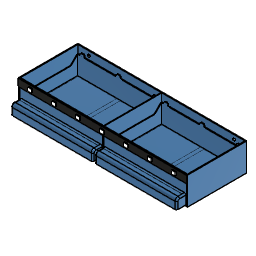
Medium_Drawer_Assembly (Autodesk Fusion 360 design; units mm, degrees)
Autodesk Fusion 360 part; units mm, degrees
note: some values were not read from the file. Set by a fixed rule: which face or edge a step refers to.
sketch "Bottom" plane through (0, 0, 0) normal (0, 0, 1) x (1, 0, 0) in component "Medium_Holder_PRINT v1"
  line L0 (0, 0) -> (232.6, 0)
  line L1 (232.6, 0) -> (232.6, 81.6)
  line L2 (232.6, 81.6) -> (0, 81.6)
  line L3 (0, 81.6) -> (0, 0)
  line L4 (1.2, 80.4) -> (231.4, 80.4)
  line L5 (231.4, 80.4) -> (231.4, 1.2)
  line L6 (231.4, 1.2) -> (1.2, 1.2)
  line L7 (1.2, 1.2) -> (1.2, 80.4)
  line L8 (3.2, 3.2) -> (3.2, 78.4)
  line L9 (33.4, 80.4) -> (34.2, 80.4)
  line L10 (34.2, 1.2) -> (33.4, 1.2)
  line L11 (66.4, 80.4) -> (67.2, 80.4)
  line L12 (67.2, 1.2) -> (66.4, 1.2)
  line L13 (99.4, 80.4) -> (100.2, 80.4)
  line L14 (100.2, 1.2032) -> (99.4, 1.2032)
  line L15 (132.4, 80.4) -> (133.2, 80.4)
  line L16 (133.2, 1.2) -> (132.4, 1.2)
  line L17 (165.4, 80.4) -> (166.2, 80.4)
  line L18 (166.2, 1.2) -> (165.4, 1.2)
  line L19 (198.4, 80.4) -> (199.2, 80.4)
  line L20 (199.2, 1.2) -> (198.4, 1.2)
  line L21 (229.4, 78.4) -> (229.4, 3.2)
  line L22 (231.4, 80.4) -> (232.2, 80.4)
  line L23 (232.2, 1.2) -> (231.4, 1.2)
  line L24 (115.9, 78.4) -> (115.9, 3.2)
  line L25 (116.7, 78.4) -> (116.7, 3.2)
  line L26 (116.7, 78.4) -> (116.7, 80.4)
  line L27 (115.9, 78.4) -> (115.9, 80.4)
  line L28 (116.7, 3.2) -> (116.7, 1.2)
  line L29 (115.9, 3.2) -> (115.9, 1.2)
  line L30 (113.9, 78.4) -> (113.9, 3.2)
  line L31 (3.2, 78.4) -> (113.9, 78.4)
  line L32 (113.9, 3.2) -> (3.2, 3.2)
  line L33 (229.4, 78.4) -> (118.7, 78.4)
  line L34 (118.7, 78.4) -> (118.7, 3.2)
  line L35 (229.4, 3.2) -> (118.7, 3.2)
  line L36 (56.2, 78.4) -> (56.2, 3.2)
  line L37 (61.2, 78.4) -> (61.2, 3.2)
  line L38 (171.7, 78.4) -> (171.7, 3.2)
  line L39 (176.7, 3.2) -> (176.7, 78.4)
  dimension "d1_3" = 1.2
  dimension "d2_3" = 1.2
  dimension "d3_3" = 1.2
  dimension "d4_3" = 1.2
  dimension "d5_3" = 2
  dimension "d8_1" = 81.6
  dimension "d52_2" = 2
  dimension "d173" = 112.7
  dimension "d174" = 112.7
  dimension "d175" = 0.8
  dimension "d190" = 2
  dimension "d191" = 2
  dimension "d192" = 2
  dimension "d193" = 2
  dimension "d194" = 2
  dimension "d195" = 2
  dimension "d203" = 5
  dimension "d204" = 53
  dimension "d206" = 5
  dimension "d207" = 53
  constraint horizontal L0
  constraint vertical L1
  constraint horizontal L2
  constraint vertical L3
  constraint coincident L0.start L3.end
  constraint horizontal L4
  constraint vertical L5
  constraint horizontal L6
  constraint vertical L7
  constraint vertical L8
  constraint horizontal L9
  constraint coincident L6 L10.start
  constraint coincident L4 L9.start
  constraint horizontal L11
  constraint horizontal L12
  constraint coincident L4 L11.start
  constraint horizontal L13
  constraint horizontal L14
  constraint coincident L4 L13.start
  constraint horizontal L15
  constraint horizontal L16
  constraint coincident L4 L15.start
  constraint horizontal L17
  constraint horizontal L18
  constraint coincident L4 L17.start
  constraint horizontal L19
  constraint horizontal L20
  constraint coincident L4 L19.start
  constraint vertical L21
  constraint horizontal L22
  constraint horizontal L23
  constraint coincident L4 L5.start
  constraint coincident L4 L26.end
  constraint perpendicular L4 L26
  constraint coincident L4 L27.end
  constraint perpendicular L4 L27
  constraint coincident L6 L28.end
  constraint perpendicular L6 L28
  constraint coincident L6 L29.end
  constraint perpendicular L6 L29
  constraint perpendicular L30 L31
  constraint perpendicular L8 L32
  constraint perpendicular L24 L33
  constraint perpendicular L34 L35
  constraint coincident L31 L36.start
  constraint coincident L32 L36.end
  constraint perpendicular L32 L36
  constraint coincident L31 L37.start
  constraint coincident L32 L37.end
  constraint perpendicular L32 L37
  constraint coincident L33 L38.start
  constraint coincident L35 L38.end
  constraint perpendicular L35 L38
  constraint coincident L35 L39.start
  constraint coincident L33 L39.end
  constraint perpendicular L33 L39
  measures "d1_3" distance of L3 L7
  measures "d2_3" distance of L2 L4
  measures "d3_3" distance of L0 L6
  measures "d4_3" distance of L1 L5
  measures "d5_3" distance of L7 L8
  measures "d8_1" distance of L0.start L2.end
  measures "d52_2" distance of L5 L21
  measures "d173" distance of L8 L24
  measures "d174" distance of L21 L25
  measures "d175" distance of L24 L25
  measures "d190" distance of L24 L30
  measures "d191" distance of L4 L31
  measures "d192" distance of L6 L32
  measures "d193" distance of L25 L34
  measures "d194" distance of L6 L35
  measures "d195" distance of L4 L33
  measures "d203" distance of L36 L37
  measures "d204" distance of L8 L36
  measures "d206" distance of L38 L39
  measures "d207" distance of L34 L38
extrude "Extrude2" add sketch "Bottom" along normal blind 38.2 contours L0 L1 L2 L3 | L4 L6 L24 L25 L26 L27 L28 L29 makes body 1 in component "Medium_Holder_PRINT v1"
sketch "Front" plane through (0, 0, 0) normal (0, -1, 0) x (1, 0, 0) in component "Medium_Holder_PRINT v1"
  line L0 (0, 0) -> (232.6, 0)
  line L1 (232.6, 0) -> (232.6, 38.2)
  line L2 (232.6, 38.2) -> (0, 38.2)
  line L3 (0, 38.2) -> (0, 0)
  line L4 (1.2, 28.2) -> (33.4, 28.2)
  line L5 (33.4, 1.2) -> (1.2, 1.2)
  line L6 (1.2, 1.2) -> (1.2, 28.2)
  line L7 (1.2, 0) -> (1.2, 38.2)
  line L8 (231.4, 28.2) -> (231.4, 1.2)
  line L9 (33.4, 28.2) -> (231.4, 28.2)
  line L10 (231.4, 1.2) -> (33.4, 1.2)
  dimension "d80" = 27
  dimension "d83" = 10
  dimension "d91" = 27
  dimension "d294" = 1.2
  constraint horizontal L4
  constraint horizontal L5
  constraint vertical L6
  constraint collinear L6 L7
  constraint vertical L8
  constraint perpendicular L8 L9
  measures "d80" distance of L4.start L5.end
  measures "d83" distance of L2 L4
  measures "d91" distance of L8.start L8.end
  measures "d294" distance of L1 L8
sketch "Back" plane through (0, 80.4, 0) normal (0, -1, 0) x (1, 0, 0) in component "Medium_Holder_PRINT v1"
  line L0 (231.4, 0) -> (231.4, 38.2)
  line L1 (115.9, 38.2) -> (1.2, 38.2)
  line L2 (1.2, 38.2) -> (1.2, 0)
  line L3 (3.2, 23) -> (3.2, 7)
  line L4 (115.9, 0) -> (115.9, 38.2)
  line L5 (116.7, 38.2) -> (116.7, 0)
  line L6 (231.4, 38.2) -> (116.7, 38.2)
  line L7 (116.7, 0) -> (231.4, 0)
  line L8 (1.2, 0) -> (115.9, 0)
  line L9 (3.2, 23) -> (6.7355, 26.5355)
  line L10 (3.2, 23) -> (8.2, 23) construction
  line L11 (6.7355, 26.5355) -> (31.7355, 26.5355)
  line L12 (31.7355, 26.5355) -> (35.2711, 23)
  line L13 (31.7355, 26.5355) -> (36.7355, 26.5355) construction
  line L14 (35.2711, 23) -> (35.2711, 7)
  line L15 (35.2711, 7) -> (31.7355, 3.4645)
  line L16 (3.2, 7) -> (6.7355, 3.4645)
  line L17 (3.2, 7) -> (8.2, 7) construction
  line L18 (6.7355, 3.4645) -> (31.7355, 3.4645)
  line L19 (43.6066, 26.5355) -> (68.6066, 26.5355)
  line L20 (40.0711, 23) -> (43.6066, 26.5355)
  line L21 (40.0711, 23) -> (40.0711, 7)
  line L22 (40.0711, 7) -> (43.6066, 3.4645)
  line L23 (43.6066, 3.4645) -> (68.6066, 3.4645)
  line L24 (72.1421, 7) -> (68.6066, 3.4645)
  line L25 (72.1421, 23) -> (72.1421, 7)
  line L26 (68.6066, 26.5355) -> (72.1421, 23)
  line L27 (80.4777, 26.5355) -> (105.4777, 26.5355)
  line L28 (76.9421, 23) -> (80.4777, 26.5355)
  line L29 (76.9421, 23) -> (76.9421, 7)
  line L30 (76.9421, 7) -> (80.4777, 3.4645)
  line L31 (80.4777, 3.4645) -> (105.4777, 3.4645)
  line L32 (109.0132, 7) -> (105.4777, 3.4645)
  line L33 (109.0132, 23) -> (109.0132, 7)
  line L34 (105.4777, 26.5355) -> (109.0132, 23)
  line L35 (127.1223, 26.5355) -> (152.1223, 26.5355)
  line L36 (123.5868, 23) -> (127.1223, 26.5355)
  line L37 (123.5868, 23) -> (123.5868, 7)
  line L38 (123.5868, 7) -> (127.1223, 3.4645)
  line L39 (127.1223, 3.4645) -> (152.1223, 3.4645)
  line L40 (155.6579, 7) -> (152.1223, 3.4645)
  line L41 (155.6579, 23) -> (155.6579, 7)
  line L42 (152.1223, 26.5355) -> (155.6579, 23)
  line L43 (163.9934, 26.5355) -> (188.9934, 26.5355)
  line L44 (160.4579, 23) -> (163.9934, 26.5355)
  line L45 (160.4579, 23) -> (160.4579, 7)
  line L46 (160.4579, 7) -> (163.9934, 3.4645)
  line L47 (163.9934, 3.4645) -> (188.9934, 3.4645)
  line L48 (192.5289, 7) -> (188.9934, 3.4645)
  line L49 (192.5289, 23) -> (192.5289, 7)
  line L50 (188.9934, 26.5355) -> (192.5289, 23)
  line L51 (200.8645, 26.5355) -> (225.8645, 26.5355)
  line L52 (197.3289, 23) -> (200.8645, 26.5355)
  line L53 (197.3289, 23) -> (197.3289, 7)
  line L54 (197.3289, 7) -> (200.8645, 3.4645)
  line L55 (200.8645, 3.4645) -> (225.8645, 3.4645)
  line L56 (229.4, 7) -> (225.8645, 3.4645)
  line L57 (229.4, 23) -> (229.4, 7)
  line L58 (225.8645, 26.5355) -> (229.4, 23)
  line L59 (232.6, 0) -> (232.6, 38.2)
  dimension "d102" = 2
  dimension "d211" = 16
  dimension "d214" = 7
  dimension "d216" = 5
  dimension "d217" = 45
  dimension "d218" = 25
  dimension "d219" = 45
  dimension "d220" = 5
  dimension "d221" = 135
  dimension "d222" = 5
  dimension "d223" = 45
  dimension "d224" = 5
  dimension "d225" = 16
  dimension "d226" = 5
  dimension "d227" = 25
  dimension "d228" = 5
  dimension "d229" = 135
  dimension "d230" = 5
  dimension "d231" = 5
  dimension "d232" = 16
  dimension "d233" = 5
  dimension "d234" = 25
  dimension "d235" = 5
  dimension "d236" = 135
  dimension "d237" = 5
  dimension "d238" = 5
  dimension "d239" = 16
  dimension "d240" = 5
  dimension "d241" = 25
  dimension "d242" = 5
  dimension "d243" = 135
  dimension "d244" = 5
  dimension "d245" = 5
  dimension "d246" = 16
  dimension "d247" = 5
  dimension "d248" = 25
  dimension "d249" = 5
  dimension "d250" = 135
  dimension "d251" = 5
  dimension "d252" = 5
  dimension "d253" = 16
  dimension "d254" = 5
  dimension "d255" = 25
  dimension "d256" = 5
  dimension "d257" = 135
  dimension "d258" = 5
  dimension "d259" = 5
  dimension "d260" = 4.8
  dimension "d261" = 4.8
  dimension "d262" = 4.8
  dimension "d263" = 4.8
  dimension "d264" = 23.0711
  dimension "d265" = 3.4645
  dimension "d266" = 32.0711
  dimension "d267" = 3.4645
  dimension "d268" = 3.2
  dimension "d269" = 6.8868
  dimension "d270" = 135
  dimension "d272" = 135
  dimension "d273" = 23.0711
  dimension "d274" = 135
  dimension "d275" = 23.0711
  dimension "d279" = 135
  dimension "d280" = 23.0711
  dimension "d281" = 135
  dimension "d283" = 32.0711
  dimension "d284" = 32.0711
  dimension "d285" = 135
  dimension "d286" = 135
  dimension "d287" = 23.0711
  dimension "d288" = 135
  dimension "d290" = 3.4645
  dimension "d292" = 135
  dimension "d297" = 3.4645
  dimension "d298" = 3.4645
  constraint parallel L2 L3
  constraint horizontal L10
  constraint horizontal L11
  constraint horizontal L13
  constraint vertical L14
  constraint horizontal L17
  constraint horizontal L19
  constraint vertical L25
  constraint horizontal L27
  constraint vertical L33
  constraint horizontal L35
  constraint vertical L41
  constraint horizontal L43
  constraint vertical L49
  constraint horizontal L51
  constraint vertical L57
  measures "d102" distance of L2 L3
  measures "d211" distance of L3.end L3.start
  measures "d214" distance of L3.end L8
  measures "d216" distance of L3.start L9.end
  measures "d217" angle of L9 L10
  measures "d218" distance of L9.end L11.end
  measures "d219" angle of L12 L13
  measures "d220" distance of L11.end L12.end
  measures "d221" angle of L14 L15
  measures "d222" distance of L14.end L15.end
  measures "d223" angle of L16 L17
  measures "d224" distance of L3.end L16.end
  measures "d225" distance of L20.start L21.end
  measures "d226" distance of L19.start L20.start
  measures "d227" distance of L19.start L19.end
  measures "d228" distance of L25.start L19.end
  measures "d229" angle of L24 L25
  measures "d230" distance of L23.end L24.start
  measures "d231" distance of L22.end L21.end
  measures "d232" distance of L28.start L29.end
  measures "d233" distance of L27.start L28.start
  measures "d234" distance of L27.start L27.end
  measures "d235" distance of L33.start L27.end
  measures "d236" angle of L32 L33
  measures "d237" distance of L31.end L32.start
  measures "d238" distance of L30.end L29.end
  measures "d239" distance of L36.start L37.end
  measures "d240" distance of L35.start L36.start
  measures "d241" distance of L35.start L35.end
  measures "d242" distance of L41.start L35.end
  measures "d243" angle of L40 L41
  measures "d244" distance of L39.end L40.start
  measures "d245" distance of L38.end L37.end
  measures "d246" distance of L44.start L45.end
  measures "d247" distance of L43.start L44.start
  measures "d248" distance of L43.start L43.end
  measures "d249" distance of L49.start L43.end
  measures "d250" angle of L48 L49
  measures "d251" distance of L47.end L48.start
  measures "d252" distance of L46.end L45.end
  measures "d253" distance of L52.start L53.end
  measures "d254" distance of L51.start L52.start
  measures "d255" distance of L51.start L51.end
  measures "d256" distance of L57.start L51.end
  measures "d257" angle of L56 L57
  measures "d258" distance of L55.end L56.start
  measures "d259" distance of L54.end L53.end
  measures "d260" distance of L14 L21
  measures "d261" distance of L25 L29
  measures "d262" distance of L49 L53
  measures "d263" distance of L41 L45
  measures "d264" distance of L35 L39
  measures "d265" distance of L7 L39
  measures "d266" distance of L37 L41
  measures "d267" distance of L7 L47
  measures "d268" distance of L57 L59
  measures "d269" distance of L5 L37
  measures "d270" angle of L43 L44
  measures "d272" angle of L43 L50
  measures "d273" distance of L43 L47
  measures "d274" angle of L51 L52
  measures "d275" distance of L51 L55
  measures "d279" angle of L35 L36
  measures "d280" distance of L27 L31
  measures "d281" angle of L27 L34
  measures "d283" distance of L29 L33
  measures "d284" distance of L21 L25
  measures "d285" angle of L19 L20
  measures "d286" angle of L19 L26
  measures "d287" distance of L19 L23
  measures "d288" angle of L20 L21
  measures "d290" distance of L8 L23
  measures "d292" angle of L15 L18
  measures "d297" distance of L8 L31
  measures "d298" distance of L7 L55
sketch "Mounting" plane through (0, 80.4, 0) normal (0, -1, 0) x (1, 0, 0) in component "Medium_Holder_PRINT v1"
  line L0 (231.4, 0) -> (231.4, 38.2)
  line L1 (115.9, 38.2) -> (1.2, 38.2)
  line L2 (1.2, 38.2) -> (1.2, 0)
  circle A0 centre (216.3, 32.2) radius 2
  circle A1 centre (16.3, 32.2) radius 2
  line L3 (115.9, 0) -> (115.9, 38.2)
  line L4 (116.7, 38.2) -> (116.7, 0)
  line L5 (231.4, 38.2) -> (116.7, 38.2)
  line L6 (116.7, 0) -> (231.4, 0)
  line L7 (1.2, 0) -> (115.9, 0)
  dimension "d165" = 4
  dimension "d166" = 4
  dimension "d167" = 15.1
  dimension "d168" = 6
  dimension "d169" = 15.1
  dimension "d170" = 6
  measures "d165" diameter of A0
  measures "d166" diameter of A1
  measures "d167" distance of L2 A1.centre
  measures "d168" distance of L1 A1.centre
  measures "d169" distance of L0 A0.centre
  measures "d170" distance of L1 A0.centre
extrude "Extrude9" cut sketch "Front" against normal up to surface (1.2 mm away) contours L4 L5 L6 L7 L8 L9 L10 bodies 1 in component "Medium_Holder_PRINT v1"
extrude "Extrude10" cut sketch "Back" against normal blind 1.2 contours L3 L9 L11 L12 L14 L15 L16 L18 | L19 L20 L21 L22 L23 L24 L25 L26 | L27 L28 L29 L30 L31 L32 L33 L34 | L35 L36 L37 L38 L39 L40 L41 L42 | L43 L44 L45 L46 L47 L48 L49 L50 | L51 L52 L53 L54 L55 L56 L57 L58 bodies 1 in component "Medium_Holder_PRINT v1"
extrude "Extrude11" cut sketch "Mounting" against normal blind 1.2 contours A0 | A1 bodies 1 in component "Medium_Holder_PRINT v1"
extrude "Extrude12" add sketch "Bottom" along normal up to surface (1.2 mm away) contours L4 L6 L7 L9 L10 L11 L12 L13 L24 L27 L29 bodies 1 in component "Medium_Holder_PRINT v1"
extrude "Extrude13" add sketch "Bottom" along normal up to surface (1.2 mm away) contours L4 L5 L6 L15 L16 L17 L18 L19 L20 L25 L26 L28 | L31 L32 L36 L37 bodies 1 in component "Medium_Holder_PRINT v1"
extrude "Extrude14" add 1 faces at (116.1667, 1.2, 19.2) along direction (0, -1, 0) up to surface (1.2 mm away) on bodies 1 bodies 1 in component "Medium_Holder_PRINT v1"
extrude "Extrude15" add sketch "Bottom" along normal blind 1.2 contours L33 L35 L38 L39 bodies 1 in component "Medium_Holder_PRINT v1"
sketch "Sketch1" plane through (0, 0, 0) normal (0, 0, 1) x (1, 0, 0) in component "Medium_Drawer_PRINT v1"
  line L0 (0, 0) -> (113.9, 0)
  line L1 (113.9, 0) -> (113.9, 80)
  line L2 (113.9, 80) -> (0, 80)
  line L3 (0, 80) -> (0, 0)
  dimension "d1_1" = 113.9
  dimension "d2_1" = 80
  constraint horizontal L0
  constraint vertical L1
  constraint horizontal L2
  constraint vertical L3
  constraint coincident L0.start L3.end
  measures "d1_1" distance of L0.start L0.end
  measures "d2_1" distance of L0.end L1.end
extrude "Extrude1" add sketch "Sketch1" along normal blind 26.2 separate body makes body 2 in component "Medium_Drawer_PRINT v1"
shell "Shell1" thickness 0.8 removed faces 1 at (37.9667, 53.3333, 26.2) on bodies 2 in component "Medium_Drawer_PRINT v1"
ref_plane "WorkPlane1" through (95.5, 40, 13.1) normal (1, 0, 0) x (0, 1, 0) in component "Medium_Drawer_PRINT v1"
sketch "Sketch3" plane through (0, 80, 0) normal (0, 1, 0) x (-1, 0, 0) in component "Medium_Drawer_PRINT v1"
  line L0 (-113.9, 0) -> (0, 0)
  line L1 (0, 0) -> (0, 26.2)
  line L2 (0, 26.2) -> (-113.9, 26.2)
  line L3 (-113.9, 26.2) -> (-113.9, 0)
  line L4 (-56.95, 26.2) -> (-56.95, 0) construction
  line L5 (-109.65, 27.45) -> (-109.65, 28.45)
  line L6 (-108.4, 29.7) -> (-105.4, 29.7)
  line L7 (-104.15, 28.45) -> (-104.15, 27.45)
  line L8 (-110.9, 26.2) -> (-102.9, 26.2)
  arc A0 (-110.9, 26.2) -> (-109.65, 27.45) centre (-110.9, 27.45) ccw
  arc A1 (-108.4, 29.7) -> (-109.65, 28.45) centre (-108.4, 28.45) ccw
  arc A2 (-104.15, 28.45) -> (-105.4, 29.7) centre (-105.4, 28.45) ccw
  arc A3 (-104.15, 27.45) -> (-102.9, 26.2) centre (-102.9, 27.45) ccw
  arc A4 (-4.25, 28.45) -> (-5.5, 29.7) centre (-5.5, 28.45) ccw
  line L9 (-5.5, 29.7) -> (-8.5, 29.7)
  arc A5 (-11, 26.2) -> (-9.75, 27.45) centre (-11, 27.45) ccw
  arc A6 (-4.25, 27.45) -> (-3, 26.2) centre (-3, 27.45) ccw
  line L10 (-4.25, 27.45) -> (-4.25, 28.45)
  line L11 (-3, 26.2) -> (-11, 26.2)
  arc A7 (-8.5, 29.7) -> (-9.75, 28.45) centre (-8.5, 28.45) ccw
  line L12 (-9.75, 28.45) -> (-9.75, 27.45)
  line L13 (-58.25, 29.7) -> (-55.25, 29.7)
  arc A8 (-58.25, 29.7) -> (-59.5, 28.45) centre (-58.25, 28.45) ccw
  line L14 (-59.5, 27.45) -> (-59.5, 28.45)
  arc A9 (-60.75, 26.2) -> (-59.5, 27.45) centre (-60.75, 27.45) ccw
  arc A10 (-54, 27.45) -> (-52.75, 26.2) centre (-52.75, 27.45) ccw
  line L15 (-60.75, 26.2) -> (-52.75, 26.2)
  line L16 (-54, 28.45) -> (-54, 27.45)
  arc A11 (-54, 28.45) -> (-55.25, 29.7) centre (-55.25, 28.45) ccw
  point P0 (-106.9, 29.7)
  point P1 (-7, 29.7)
  dimension "d18_1" = 7
  dimension "d19_1" = 3.5
  dimension "d20_1" = 5.5
  dimension "d21_1" = 1.25
  dimension "d62" = 3.5
  dimension "d63" = 5.5
  dimension "d64" = 1.25
  dimension "d65" = 114.3
  dimension "d66" = 44.65
  dimension "d67" = 44.8
  dimension "d68" = 8
  dimension "d69" = 1.25
  dimension "d70" = 3
  dimension "d71" = 1.25
  dimension "d72" = 1.25
  dimension "d73" = 1.25
  dimension "d74" = 3.5
  constraint midpoint L2 L4.start
  constraint perpendicular L2 L4
  constraint coincident L0 L4.end
  constraint horizontal L6
  constraint tangent L6 A1
  constraint tangent L5 A1
  constraint tangent L5 A0
  constraint tangent L6 A2
  constraint tangent L7 A2
  constraint tangent L7 A3
  constraint tangent L8 A3
  constraint tangent L8 A0
  constraint equal A0 A1
  constraint equal A1 A2
  constraint equal A2 A3
  constraint collinear L2 L8
  constraint vertical L7
  constraint vertical L5
  constraint midpoint L6 P0
  constraint symmetric L4 L5.start A6.start
  constraint symmetric L4 L5.end A4.start
  constraint symmetric L4 L6.start A4.end
  constraint symmetric L4 L6.end L9.end
  constraint symmetric L4 L7.start A7.end
  constraint symmetric L4 L7.end A5.end
  constraint symmetric L4 L8.start A6.end
  constraint symmetric L4 L8.end A5.start
  constraint symmetric L4 P0 P1
  constraint symmetric L4 A0 A6
  constraint symmetric L4 A1 A4
  constraint symmetric L4 A2 A7
  constraint symmetric L4 A3 A5
  constraint horizontal L13
  constraint tangent L13 A8
  constraint tangent A8 L14
  constraint tangent L14 A9
  constraint tangent L13 A11
  constraint tangent L16 A11
  constraint tangent A10 L16
  constraint tangent A10 L15
  constraint tangent A9 L15
  constraint equal A8 A9
  constraint equal A8 A11
  constraint equal A10 A11
  constraint vertical L16
  constraint vertical L14
  measures "d18_1" distance of L3 P0
  measures "d19_1" distance of L6 L8
  measures "d20_1" distance of L5 L7
  measures "d21_1" radius of A0
  measures "d62" distance of L13 L15
  measures "d63" distance of L14 L16
  measures "d64" radius of A9
  measures "d66" distance of L7 L14
  measures "d68" distance of A9.start A10.end
  measures "d69" radius of A10
  measures "d70" distance of L13.start L13.end
  measures "d71" radius of A11
  measures "d72" radius of A9
  measures "d73" radius of A8
  measures "d74" distance of L4.start L13
extrude "Extrude3" add sketch "Sketch3" against normal blind 0.8 contours L2 L5 L6 L7 L8 A0 A1 A2 A3 | L2 A4 L9 A5 A6 L10 L11 A7 L12 | L2 L13 A8 L14 A9 A10 L15 L16 A11 bodies 2 in component "Medium_Drawer_PRINT v1"
sketch "Sketch4" plane through (113.9, 0, 0) normal (1, 0, 0) x (0, 1, 0) in component "Medium_Drawer_PRINT v1"
  line L0 (0, 0) -> (80, 0)
  line L1 (80, 0) -> (80, 26.2)
  line L2 (80, 26.2) -> (0, 26.2)
  line L3 (0, 26.2) -> (0, 0)
  line L4 (0.9071, 26.2) -> (10.1071, 17)
  line L5 (0.9071, 26.2) -> (7.8528, 26.2) construction
  line L6 (10.1071, 17) -> (69.7311, 17)
  line L7 (69.7311, 17) -> (78.9311, 26.2)
  line L8 (78.9311, 26.2) -> (0.9071, 26.2)
  dimension "d24_1" = 45
  dimension "d25_1" = 135
  dimension "d26_1" = 17
  constraint horizontal L5
  constraint coincident L2 L4.start
  constraint horizontal L6
  constraint coincident L2 L7.end
  measures "d24_1" angle of L4 L5
  measures "d25_1" angle of L6 L7
  measures "d26_1" distance of L0 L6
extrude "Extrude4" cut sketch "Sketch4" against normal up to surface (113.9 mm away) contours L2 L4 L6 L7 L8 bodies 2 in component "Medium_Drawer_PRINT v1"
extrude "Extrude5" add 1 faces at (58.2167, 79.2, 9.2667) along direction (0, -1, 0) blind 0.4 on bodies 2 bodies 2 in component "Medium_Drawer_PRINT v1"
sketch "Sketch5" plane through (0, 0, 0) normal (0, -1, 0) x (1, 0, 0) in component "Medium_Drawer_PRINT v1"
  line L0 (0, 0) -> (113.9, 0)
  line L1 (113.9, 0) -> (113.9, 26.2)
  line L2 (113.9, 26.2) -> (0, 26.2)
  line L3 (0, 26.2) -> (0, 0)
  line L4 (0.5, 13.8) -> (113.4, 13.8)
  line L5 (113.4, 13.8) -> (113.4, 13)
  line L6 (113.4, 13) -> (0.5, 13)
  line L7 (0.5, 13) -> (0.5, 13.8)
  dimension "d31_1" = 0.5
  dimension "d32_1" = 0.5
  dimension "d33_1" = 0.8
  dimension "d34" = 13
  constraint horizontal L4
  constraint vertical L5
  constraint horizontal L6
  constraint vertical L7
  measures "d31_1" distance of L3 L7
  measures "d32_1" distance of L1 L5
  measures "d33_1" distance of L4 L6
  measures "d34" distance of L0 L6
extrude "Extrude6" add sketch "Sketch5" along normal blind 13 contours L4 L5 L6 L7 bodies 2 in component "Medium_Drawer_PRINT v1"
sketch "Sketch6" plane through (0, 0, 13) normal (0, 0, -1) x (1, 0, 0) in component "Medium_Drawer_PRINT v1"
  line L0 (0.5, 0) -> (113.4, 0)
  line L1 (113.4, 0) -> (113.4, 13)
  line L2 (113.4, 13) -> (0.5, 13)
  line L3 (0.5, 13) -> (0.5, 0)
  line L4 (0.5, 13) -> (31.3, 13)
  line L5 (31.3, 12.2) -> (0.5, 12.2)
  line L6 (0.5, 12.2) -> (0.5, 13)
  line L7 (31.3, 13) -> (113.4, 13)
  line L8 (31.3, 12.2) -> (113.4, 12.2)
  line L9 (113.4, 12.2) -> (113.4, 13)
  dimension "d37" = 0.8
  constraint horizontal L4
  constraint horizontal L5
  constraint vertical L6
  constraint coincident L2.end L3.start
  constraint coincident L1.end L2.start
  constraint coincident L1 L8.end
  constraint perpendicular L1 L8
  measures "d37" distance of L2.end L5.end
extrude "Extrude7" add sketch "Sketch6" along normal blind 13 contours L1 L2 L3 L4 L5 L6 L7 L8 L9 bodies 2 in component "Medium_Drawer_PRINT v1"
sketch "Sketch8" plane through (0, 0, 13) normal (0, 0, -1) x (1, 0, 0) in component "Medium_Drawer_PRINT v1"
  line L0 (113.4, 12.2) -> (0.5, 12.2)
  line L1 (0.5, 12.2) -> (0.5, 0)
  line L2 (0.5, 0) -> (113.4, 0)
  line L3 (113.4, 0) -> (113.4, 12.2)
  line L4 (1.3, 0) -> (0.5, 0)
  line L5 (0.5, 0) -> (0.5, 12.2)
  line L6 (0.5, 12.2) -> (1.3, 12.2)
  line L7 (1.3, 12.2) -> (1.3, 0)
  line L8 (113.4, 0) -> (112.6, 0)
  line L9 (112.6, 0) -> (112.6, 12.2)
  line L10 (112.6, 12.2) -> (113.4, 12.2)
  line L11 (113.4, 12.2) -> (113.4, 0)
  dimension "d45" = 0.8
  dimension "d46" = 0.8
  constraint horizontal L4
  constraint vertical L5
  constraint horizontal L6
  constraint vertical L7
  constraint coincident L0.end L1.start
  constraint coincident L2 L4.start
  constraint horizontal L8
  constraint vertical L9
  constraint horizontal L10
  constraint vertical L11
  constraint coincident L0 L9.end
  constraint coincident L2.end L3.start
  measures "d45" distance of L9.end L0.start
  measures "d46" distance of L0.end L6.end
extrude "Extrude9'" add sketch "Sketch8" along normal blind 13 contours L0 L2 L3 L8 L9 L10 L11 | L0 L1 L2 L4 L5 L6 L7 bodies 2 in component "Medium_Drawer_PRINT v1"
fillet "Fillet2" radius 4 2 edges at (56.95, -12.2, 13) (56.95, -13, 13.8) on bodies 2 in component "Medium_Drawer_PRINT v1"
chamfer "Chamfer1" distance 3 angle 45 1 edges at (56.95, 0, 13) on bodies 2 in component "Medium_Drawer_PRINT v1"
fillet "Fillet4" radius 2 6 edges at (1.3, -12.2, 4.5) (1.3, -11.0284, 11.8284) (1.3, -5.6, 13) (0.5, -4.5, 13.8) (0.5, -11.8284, 12.6284) (0.5, -13, 4.9) on bodies 2 in component "Medium_Drawer_PRINT v1"
fillet "Fillet5" radius 2 3 edges at (112.6, -5.6, 13) (112.6, -11.0284, 11.8284) (112.6, -12.2, 4.5) on bodies 2 in component "Medium_Drawer_PRINT v1"
fillet "Fillet6" radius 2 3 edges at (113.4, -4.5, 13.8) (113.4, -11.8284, 12.6284) (113.4, -13, 4.9) on bodies 2 in component "Medium_Drawer_PRINT v1"
sketch "Sketch1 (2)" plane through (0, 0, 0) normal (0, 0, 1) x (1, 0, 0) in component "Medium_Drawer_PRINT v3"
  line L0 (0, 0) -> (113.9, 0)
  line L1 (113.9, 0) -> (113.9, 80)
  line L2 (113.9, 80) -> (0, 80)
  line L3 (0, 80) -> (0, 0)
  dimension "d1_2" = 113.9
  dimension "d2_2" = 80
  constraint horizontal L0
  constraint vertical L1
  constraint horizontal L2
  constraint vertical L3
  constraint coincident L0.start L3.end
  measures "d1_2" distance of L0.start L0.end
  measures "d2_2" distance of L0.end L1.end
extrude "Extrude1'" add sketch "Sketch1 (2)" along normal blind 26.2 separate body makes body 3 in component "Medium_Drawer_PRINT v3"
shell "Shell1'" thickness 0.8 removed faces 1 at (37.9667, 53.3333, 26.2) on bodies 3 in component "Medium_Drawer_PRINT v3"
ref_plane "WorkPlane1" through (95.5, 40, 13.1) normal (1, 0, 0) x (0, 1, 0) in component "Medium_Drawer_PRINT v3"
sketch "Sketch3 (2)" plane through (0, 80, 0) normal (0, 1, 0) x (-1, 0, 0) in component "Medium_Drawer_PRINT v3"
  line L0 (-113.9, 0) -> (0, 0)
  line L1 (0, 0) -> (0, 26.2)
  line L2 (0, 26.2) -> (-113.9, 26.2)
  line L3 (-113.9, 26.2) -> (-113.9, 0)
  line L4 (-56.95, 26.2) -> (-56.95, 0) construction
  line L5 (-109.65, 27.45) -> (-109.65, 28.45)
  line L6 (-108.4, 29.7) -> (-105.4, 29.7)
  line L7 (-104.15, 28.45) -> (-104.15, 27.45)
  line L8 (-110.9, 26.2) -> (-102.9, 26.2)
  arc A0 (-110.9, 26.2) -> (-109.65, 27.45) centre (-110.9, 27.45) ccw
  arc A1 (-108.4, 29.7) -> (-109.65, 28.45) centre (-108.4, 28.45) ccw
  arc A2 (-104.15, 28.45) -> (-105.4, 29.7) centre (-105.4, 28.45) ccw
  arc A3 (-104.15, 27.45) -> (-102.9, 26.2) centre (-102.9, 27.45) ccw
  arc A4 (-4.25, 28.45) -> (-5.5, 29.7) centre (-5.5, 28.45) ccw
  line L9 (-5.5, 29.7) -> (-8.5, 29.7)
  arc A5 (-11, 26.2) -> (-9.75, 27.45) centre (-11, 27.45) ccw
  arc A6 (-4.25, 27.45) -> (-3, 26.2) centre (-3, 27.45) ccw
  line L10 (-4.25, 27.45) -> (-4.25, 28.45)
  line L11 (-3, 26.2) -> (-11, 26.2)
  arc A7 (-8.5, 29.7) -> (-9.75, 28.45) centre (-8.5, 28.45) ccw
  line L12 (-9.75, 28.45) -> (-9.75, 27.45)
  line L13 (-58.25, 29.7) -> (-55.25, 29.7)
  arc A8 (-58.25, 29.7) -> (-59.5, 28.45) centre (-58.25, 28.45) ccw
  line L14 (-59.5, 27.45) -> (-59.5, 28.45)
  arc A9 (-60.75, 26.2) -> (-59.5, 27.45) centre (-60.75, 27.45) ccw
  arc A10 (-54, 27.45) -> (-52.75, 26.2) centre (-52.75, 27.45) ccw
  line L15 (-60.75, 26.2) -> (-52.75, 26.2)
  line L16 (-54, 28.45) -> (-54, 27.45)
  arc A11 (-54, 28.45) -> (-55.25, 29.7) centre (-55.25, 28.45) ccw
  point P0 (-106.9, 29.7)
  point P1 (-7, 29.7)
  dimension "d18_2" = 7
  dimension "d19_2" = 3.5
  dimension "d20_2" = 5.5
  dimension "d21_2" = 1.25
  dimension "d62_1" = 3.5
  dimension "d63_1" = 5.5
  dimension "d64_1" = 1.25
  dimension "d65_1" = 114.3
  dimension "d66_1" = 44.65
  dimension "d67_1" = 44.8
  dimension "d68_1" = 8
  dimension "d69_1" = 1.25
  dimension "d70_1" = 3
  dimension "d71_1" = 1.25
  dimension "d72_1" = 1.25
  dimension "d73_1" = 1.25
  dimension "d74_1" = 3.5
  constraint midpoint L2 L4.start
  constraint perpendicular L2 L4
  constraint coincident L0 L4.end
  constraint horizontal L6
  constraint tangent L6 A1
  constraint tangent L5 A1
  constraint tangent L5 A0
  constraint tangent L6 A2
  constraint tangent L7 A2
  constraint tangent L7 A3
  constraint tangent L8 A3
  constraint tangent L8 A0
  constraint equal A0 A1
  constraint equal A1 A2
  constraint equal A2 A3
  constraint collinear L2 L8
  constraint vertical L7
  constraint vertical L5
  constraint midpoint L6 P0
  constraint symmetric L4 L5.start A6.start
  constraint symmetric L4 L5.end A4.start
  constraint symmetric L4 L6.start A4.end
  constraint symmetric L4 L6.end L9.end
  constraint symmetric L4 L7.start A7.end
  constraint symmetric L4 L7.end A5.end
  constraint symmetric L4 L8.start A6.end
  constraint symmetric L4 L8.end A5.start
  constraint symmetric L4 P0 P1
  constraint symmetric L4 A0 A6
  constraint symmetric L4 A1 A4
  constraint symmetric L4 A2 A7
  constraint symmetric L4 A3 A5
  constraint horizontal L13
  constraint tangent L13 A8
  constraint tangent A8 L14
  constraint tangent L14 A9
  constraint tangent L13 A11
  constraint tangent L16 A11
  constraint tangent A10 L16
  constraint tangent A10 L15
  constraint tangent A9 L15
  constraint equal A8 A9
  constraint equal A8 A11
  constraint equal A10 A11
  constraint vertical L16
  constraint vertical L14
  measures "d18_2" distance of L3 P0
  measures "d19_2" distance of L6 L8
  measures "d20_2" distance of L5 L7
  measures "d21_2" radius of A0
  measures "d62_1" distance of L13 L15
  measures "d63_1" distance of L14 L16
  measures "d64_1" radius of A9
  measures "d66_1" distance of L7 L14
  measures "d68_1" distance of A9.start A10.end
  measures "d69_1" radius of A10
  measures "d70_1" distance of L13.start L13.end
  measures "d71_1" radius of A11
  measures "d72_1" radius of A9
  measures "d73_1" radius of A8
  measures "d74_1" distance of L4.start L13
extrude "Extrude3'" add sketch "Sketch3 (2)" against normal blind 0.8 contours L2 L5 L6 L7 L8 A0 A1 A2 A3 | L2 A4 L9 A5 A6 L10 L11 A7 L12 | L2 L13 A8 L14 A9 A10 L15 L16 A11 bodies 3 in component "Medium_Drawer_PRINT v3"
sketch "Sketch4 (2)" plane through (113.9, 0, 0) normal (1, 0, 0) x (0, 1, 0) in component "Medium_Drawer_PRINT v3"
  line L0 (0, 0) -> (80, 0)
  line L1 (80, 0) -> (80, 26.2)
  line L2 (80, 26.2) -> (0, 26.2)
  line L3 (0, 26.2) -> (0, 0)
  line L4 (0.9071, 26.2) -> (10.1071, 17)
  line L5 (0.9071, 26.2) -> (7.8528, 26.2) construction
  line L6 (10.1071, 17) -> (69.7311, 17)
  line L7 (69.7311, 17) -> (78.9311, 26.2)
  line L8 (78.9311, 26.2) -> (0.9071, 26.2)
  dimension "d24_2" = 45
  dimension "d25_2" = 135
  dimension "d26_2" = 17
  constraint horizontal L5
  constraint coincident L2 L4.start
  constraint horizontal L6
  constraint coincident L2 L7.end
  measures "d24_2" angle of L4 L5
  measures "d25_2" angle of L6 L7
  measures "d26_2" distance of L0 L6
extrude "Extrude4'" cut sketch "Sketch4 (2)" against normal up to surface (113.9 mm away) contours L2 L4 L6 L7 L8 bodies 3 in component "Medium_Drawer_PRINT v3"
extrude "Extrude5'" add 1 faces at (58.2167, 79.2, 9.2667) along direction (0, -1, 0) blind 0.4 on bodies 3 bodies 3 in component "Medium_Drawer_PRINT v3"
sketch "Sketch5 (2)" plane through (0, 0, 0) normal (0, -1, 0) x (1, 0, 0) in component "Medium_Drawer_PRINT v3"
  line L0 (0, 0) -> (113.9, 0)
  line L1 (113.9, 0) -> (113.9, 26.2)
  line L2 (113.9, 26.2) -> (0, 26.2)
  line L3 (0, 26.2) -> (0, 0)
  line L4 (0.5, 13.8) -> (113.4, 13.8)
  line L5 (113.4, 13.8) -> (113.4, 13)
  line L6 (113.4, 13) -> (0.5, 13)
  line L7 (0.5, 13) -> (0.5, 13.8)
  dimension "d31_2" = 0.5
  dimension "d32_2" = 0.5
  dimension "d33_2" = 0.8
  dimension "d34_1" = 13
  constraint horizontal L4
  constraint vertical L5
  constraint horizontal L6
  constraint vertical L7
  measures "d31_2" distance of L3 L7
  measures "d32_2" distance of L1 L5
  measures "d33_2" distance of L4 L6
  measures "d34_1" distance of L0 L6
extrude "Extrude6'" add sketch "Sketch5 (2)" along normal blind 13 contours L4 L5 L6 L7 bodies 3 in component "Medium_Drawer_PRINT v3"
sketch "Sketch6 (2)" plane through (0, 0, 13) normal (0, 0, -1) x (1, 0, 0) in component "Medium_Drawer_PRINT v3"
  line L0 (0.5, 0) -> (113.4, 0)
  line L1 (113.4, 0) -> (113.4, 13)
  line L2 (113.4, 13) -> (0.5, 13)
  line L3 (0.5, 13) -> (0.5, 0)
  line L4 (0.5, 13) -> (31.3, 13)
  line L5 (31.3, 12.2) -> (0.5, 12.2)
  line L6 (0.5, 12.2) -> (0.5, 13)
  line L7 (31.3, 13) -> (113.4, 13)
  line L8 (31.3, 12.2) -> (113.4, 12.2)
  line L9 (113.4, 12.2) -> (113.4, 13)
  dimension "d37_1" = 0.8
  constraint horizontal L4
  constraint horizontal L5
  constraint vertical L6
  constraint coincident L2.end L3.start
  constraint coincident L1.end L2.start
  constraint coincident L1 L8.end
  constraint perpendicular L1 L8
  measures "d37_1" distance of L2.end L5.end
extrude "Extrude7'" add sketch "Sketch6 (2)" along normal blind 13 contours L1 L2 L3 L4 L5 L6 L7 L8 L9 bodies 3 in component "Medium_Drawer_PRINT v3"
sketch "Sketch8 (2)" plane through (0, 0, 13) normal (0, 0, -1) x (1, 0, 0) in component "Medium_Drawer_PRINT v3"
  line L0 (113.4, 12.2) -> (0.5, 12.2)
  line L1 (0.5, 12.2) -> (0.5, 0)
  line L2 (0.5, 0) -> (113.4, 0)
  line L3 (113.4, 0) -> (113.4, 12.2)
  line L4 (1.3, 0) -> (0.5, 0)
  line L5 (0.5, 0) -> (0.5, 12.2)
  line L6 (0.5, 12.2) -> (1.3, 12.2)
  line L7 (1.3, 12.2) -> (1.3, 0)
  line L8 (113.4, 0) -> (112.6, 0)
  line L9 (112.6, 0) -> (112.6, 12.2)
  line L10 (112.6, 12.2) -> (113.4, 12.2)
  line L11 (113.4, 12.2) -> (113.4, 0)
  dimension "d45_1" = 0.8
  dimension "d46_1" = 0.8
  constraint horizontal L4
  constraint vertical L5
  constraint horizontal L6
  constraint vertical L7
  constraint coincident L0.end L1.start
  constraint coincident L2 L4.start
  constraint horizontal L8
  constraint vertical L9
  constraint horizontal L10
  constraint vertical L11
  constraint coincident L0 L9.end
  constraint coincident L2.end L3.start
  measures "d45_1" distance of L9.end L0.start
  measures "d46_1" distance of L0.end L6.end
extrude "Extrude9''" add sketch "Sketch8 (2)" along normal blind 13 contours L0 L2 L3 L8 L9 L10 L11 | L0 L1 L2 L4 L5 L6 L7 bodies 3 in component "Medium_Drawer_PRINT v3"
fillet "Fillet2'" radius 4 2 edges at (56.95, -12.2, 13) (56.95, -13, 13.8) on bodies 3 in component "Medium_Drawer_PRINT v3"
chamfer "Chamfer1'" distance 3 angle 45 1 edges at (56.95, 0, 13) on bodies 3 in component "Medium_Drawer_PRINT v3"
fillet "Fillet4'" radius 2 6 edges at (1.3, -12.2, 4.5) (1.3, -11.0284, 11.8284) (1.3, -5.6, 13) (0.5, -4.5, 13.8) (0.5, -11.8284, 12.6284) (0.5, -13, 4.9) on bodies 3 in component "Medium_Drawer_PRINT v3"
fillet "Fillet5'" radius 2 3 edges at (112.6, -5.6, 13) (112.6, -11.0284, 11.8284) (112.6, -12.2, 4.5) on bodies 3 in component "Medium_Drawer_PRINT v3"
fillet "Fillet6'" radius 2 3 edges at (113.4, -4.5, 13.8) (113.4, -11.8284, 12.6284) (113.4, -13, 4.9) on bodies 3 in component "Medium_Drawer_PRINT v3"
sketch "Sketch1 (3)" plane through (0, 0, 0) normal (0, -1, 0) x (1, 0, 0)
  line L0 (115.9, 1.2) -> (1.2, 1.2)
  line L1 (1.2, 1.2) -> (1.2, 28.2)
  line L2 (1.2, 28.2) -> (115.9, 28.2)
  line L3 (115.9, 28.2) -> (115.9, 1.2)
  line L4 (116.7, 1.2) -> (116.7, 28.2)
  line L5 (116.7, 28.2) -> (231.4, 28.2)
  line L6 (231.4, 28.2) -> (231.4, 1.2)
  line L7 (231.4, 1.2) -> (116.7, 1.2)
  line L8 (0, 0) -> (232.6, 0)
  line L9 (232.6, 0) -> (232.6, 38.2)
  line L10 (232.6, 38.2) -> (0, 38.2)
  line L11 (0, 38.2) -> (0, 0)
  line L12 (0, 38.2) -> (232.6, 38.2)
  line L13 (232.6, 38.2) -> (232.6, 28.2)
  line L14 (232.6, 28.2) -> (0, 28.2)
  line L15 (0, 28.2) -> (0, 38.2)
  dimension "d1" = 10
  constraint horizontal L12
  constraint vertical L13
  constraint horizontal L14
  constraint vertical L15
  constraint coincident L9 L13.end
  constraint coincident L10.end L11.start
  measures "d1" distance of L9.end L13.end
extrude "Extrude1''" add sketch "Sketch1 (3)" along normal blind 1 separate body contours L2 L5 L9 L10 L11 L12 L13 L14 L15 makes body 4
sketch "Sketch2" plane through (0, -1, 0) normal (0, -1, 0) x (1, 0, 0)
  line L0 (0, 28.2) -> (232.6, 28.2)
  line L1 (232.6, 28.2) -> (232.6, 38.2)
  line L2 (232.6, 38.2) -> (0, 38.2)
  line L3 (0, 38.2) -> (0, 28.2)
  line L4 (15, 35.7) -> (20, 35.7)
  line L5 (20, 35.7) -> (20, 30.7)
  line L6 (20, 30.7) -> (15, 30.7)
  line L7 (15, 30.7) -> (15, 35.7)
  line L8 (48, 35.7) -> (53, 35.7)
  line L9 (53, 35.7) -> (53, 30.7)
  line L10 (53, 30.7) -> (48, 30.7)
  line L11 (48, 30.7) -> (48, 35.7)
  line L12 (81, 35.7) -> (86, 35.7)
  line L13 (86, 35.7) -> (86, 30.7)
  line L14 (86, 30.7) -> (81, 30.7)
  line L15 (81, 30.7) -> (81, 35.7)
  line L16 (114, 35.7) -> (119, 35.7)
  line L17 (119, 35.7) -> (119, 30.7)
  line L18 (119, 30.7) -> (114, 30.7)
  line L19 (114, 30.7) -> (114, 35.7)
  line L20 (147, 35.7) -> (152, 35.7)
  line L21 (152, 35.7) -> (152, 30.7)
  line L22 (152, 30.7) -> (147, 30.7)
  line L23 (147, 30.7) -> (147, 35.7)
  line L24 (180, 35.7) -> (185, 35.7)
  line L25 (185, 35.7) -> (185, 30.7)
  line L26 (185, 30.7) -> (180, 30.7)
  line L27 (180, 30.7) -> (180, 35.7)
  line L28 (213, 35.7) -> (218, 35.7)
  line L29 (218, 35.7) -> (218, 30.7)
  line L30 (218, 30.7) -> (213, 30.7)
  line L31 (213, 30.7) -> (213, 35.7)
  dimension "d4" = 5
  dimension "d5" = 5
  dimension "d6" = 5
  dimension "d7" = 5
  dimension "d8" = 5
  dimension "d9" = 5
  dimension "d10" = 28
  dimension "d11" = 5
  dimension "d12" = 5
  dimension "d13" = 5
  dimension "d14" = 28
  dimension "d15" = 15
  dimension "d16" = 28
  dimension "d17" = 2.5
  dimension "d18" = 2.5
  dimension "d19" = 2.5
  dimension "d20" = 2.5
  dimension "d21" = 2.5
  dimension "d22" = 5
  dimension "d23" = 5
  dimension "d24" = 28
  dimension "d25" = 5
  dimension "d26" = 2.5
  dimension "d27" = 28
  dimension "d28" = 5
  dimension "d29" = 5
  dimension "d30" = 2.5
  dimension "d31" = 28
  constraint horizontal L4
  constraint vertical L5
  constraint horizontal L6
  constraint vertical L7
  constraint horizontal L8
  constraint vertical L9
  constraint horizontal L10
  constraint vertical L11
  constraint horizontal L12
  constraint vertical L13
  constraint horizontal L14
  constraint vertical L15
  constraint horizontal L16
  constraint vertical L17
  constraint horizontal L18
  constraint vertical L19
  constraint horizontal L20
  constraint vertical L21
  constraint horizontal L22
  constraint vertical L23
  constraint horizontal L24
  constraint vertical L25
  constraint horizontal L26
  constraint vertical L27
  constraint horizontal L28
  constraint vertical L29
  constraint horizontal L30
  constraint vertical L31
  measures "d4" distance of L4.start L4.end
  measures "d5" distance of L8.start L8.end
  measures "d6" distance of L12.start L12.end
  measures "d7" distance of L16.start L16.end
  measures "d8" distance of L20.start L20.end
  measures "d9" distance of L24.start L24.end
  measures "d10" distance of L5 L11
  measures "d11" distance of L4.end L5.end
  measures "d12" distance of L8.end L9.end
  measures "d13" distance of L12.end L13.end
  measures "d14" distance of L9 L15
  measures "d15" distance of L3 L7
  measures "d16" distance of L13 L19
  measures "d17" distance of L2 L12
  measures "d18" distance of L2 L16
  measures "d19" distance of L2 L8
  measures "d20" distance of L2 L4
  measures "d21" distance of L2 L20
  measures "d22" distance of L16.start L18.end
  measures "d23" distance of L20.end L21.end
  measures "d24" distance of L17 L23
  measures "d25" distance of L24.end L25.end
  measures "d26" distance of L2 L24
  measures "d27" distance of L21 L27
  measures "d28" distance of L28.start L28.end
  measures "d29" distance of L28.end L29.end
  measures "d30" distance of L2 L28
  measures "d31" distance of L25 L31
extrude "Extrude3''" add sketch "Sketch2" along normal blind 1.5 contours L4 L5 L6 L7 | L8 L9 L10 L11 | L12 L13 L14 L15 | L16 L17 L18 L19 | L20 L21 L22 L23 | L24 L25 L26 L27 | L28 L29 L30 L31 bodies 4
component "Medium_Drawer_PRINT v1" placed x (1, 0, 0) y (0, 1, 0) z (0, 0, 1) at (1.5, 0, 1.5)
component "Medium_Drawer_PRINT v3" placed x (1, 0, 0) y (0, 1, 0) z (0, 0, 1) at (117, 0, 1.5)
component "Medium_Holder_PRINT v1" placed x (1, 0, 0) y (0, 1, 0) z (0, 0, 1) at (0, 0, 0)
equation "d1_1 = 114.7 mm - 0.8 mm"
equation "d1_2 = 114.7 mm - 0.8 mm"
equation "d173 = ( ( 226.2 / 2 ) * 1 mm ) - 0.4 mm"
equation "d174 = ( ( 226.2 / 2 ) * 1 mm ) - 0.4 mm"
